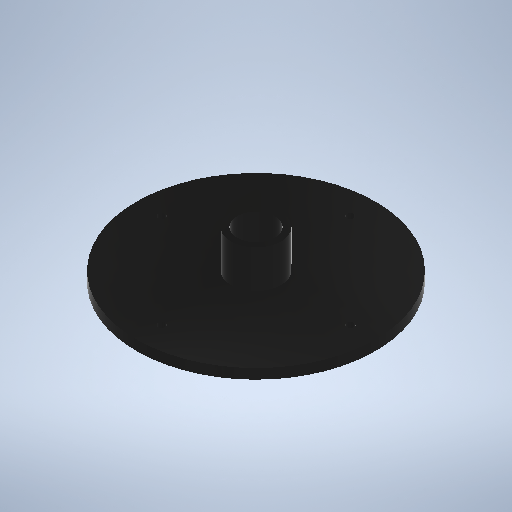
# Autodesk Inventor part: TAMPA
Saved by Autodesk Inventor 2025 (Build 290162000, 162)
## iProperties
Created: 2026-10-05
Part Number: TAMPA
Material: Acetal Resin, Black
Document SubType Name: Modeling
Designer: 34275214862
Density: 1.425 g/cm^3
Appearance: Smooth - Black
Author: 34275214862
Autodesk Inventor part; units mm, degrees
ref_plane "YZ Plane" through (0, 0, 0) normal (1, 0, 0) x (0, 1, 0)
ref_plane "XZ Plane" through (0, 0, 0) normal (0, 1, 0) x (-1, 0, 0)
ref_plane "XY Plane" through (0, 0, 0) normal (0, 0, 1) x (1, 0, 0)
sketch "Sketch1" plane through (0, 0, 0) normal (0, 0, 1) x (1, 0, 0)
  line L0 (-20, 0) -> (-95, 0)
  line L1 (-95, 0) -> (-95, -8)
  line L2 (-95, -8) -> (-84, -8)
  line L3 (-84, -8) -> (-84, -10)
  line L4 (-84, -10) -> (-15, -10)
  line L5 (0, -10) -> (0, 0)
  line L6 (-20, 0) -> (-20, 30)
  line L7 (-20, 30) -> (-15, 30)
  line L8 (-15, 30) -> (-15, -10)
  dimension "d0" = 190
  dimension "d1" = 168
  dimension "d2" = 8
  dimension "d3" = 2
  dimension "d4" = 30
  dimension "d5" = 5
  dimension "d6" = 30
  constraints: 18 end point, 7 perpendicular, 2 horizontal alignment, 1 horizontal, 1 vertical
  measures "d0" diameter of L1 L5
  measures "d1" diameter of L3 L5
  measures "d2" distance of L0.end L1.end
  measures "d3" distance between parallel lines of L2 L4
  measures "d4" diameter of L8 L5
  measures "d5" distance of L6.end L7.end
  measures "d6" distance between parallel lines of L7 L0
revolve "Revolution1" add sketch "Sketch1" angle 360 about axis through (0, -10, 0) along (0, 1, 0)
sketch "Sketch2" plane through (0, 0, 0) normal (0, 1, 0) x (1, 0, 0)
  point P0 (0, 0)
  point P1 (0, 75)
  point P2 (-75, 0)
  point P3 (0, -75)
  point P4 (75, 0)
  dimension "d8" = 75
  dimension "d11" = 360
  constraints: 1 vertical alignment, 5 other
  measures "d8" distance of point (0, 0) point (0, 75)
hole "Hole1" at (0, 0, -75) at (-75, 0, 0) at (0, 0, 75) at (75, 0, 0) direction (0, -1, 0) diameter 6 depth 8 tip angle 118
body "Solid1"
